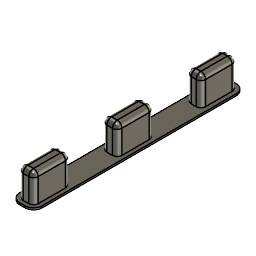
Buttons (Autodesk Fusion 360 design; units mm, degrees)
part number: 2026-07-23-09-26-05-520
Autodesk Fusion 360 part; units mm, degrees
sketch "Sketch1" plane through (0, 0, 0) normal (0, 0, 1) x (1, 0, 0)
  line L0 (-1.2, -11.25) -> (-1.2, 11.25)
  line L1 (-1.2, 11.25) -> (1.2, 11.25)
  line L2 (1.2, 11.25) -> (1.2, -11.25)
  line L3 (1.2, -11.25) -> (-1.2, -11.25)
  line L4 (0.76, 10.81) -> (0.76, 6.99)
  line L5 (-0.76, 6.99) -> (0.76, 6.99)
  line L6 (-0.76, 6.99) -> (-0.76, 10.81)
  line L7 (-0.76, 10.81) -> (0.76, 10.81)
  line L8 (-0.8, 1.95) -> (0.8, 1.95)
  line L9 (-0.8, -1.95) -> (-0.8, 1.95)
  line L10 (-0.8, -1.95) -> (0.8, -1.95)
  line L11 (0.8, 1.95) -> (0.8, -1.95)
  line L12 (-0.8, -6.95) -> (0.8, -6.95)
  line L13 (-0.8, -10.85) -> (-0.8, -6.95)
  line L14 (0.8, -10.85) -> (-0.8, -10.85)
  line L15 (0.8, -6.95) -> (0.8, -10.85)
extrude "Extrude1" add sketch "Sketch1" against normal blind 0.2 contours L0 L1 L2 L3 | L4 L5 L6 L7 | L8 L9 L10 L11 | L12 L13 L14 L15
extrude "Extrude2" add sketch "Sketch1" along normal blind 3 contours L4 L5 L6 L7 | L8 L9 L10 L11 | L12 L13 L14 L15
fillet "Fillet2" radius 0.5 24 edges at (-0.8, -10.85, 1.5) (-0.8, -6.95, 1.5) (0.8, -6.95, 1.5) (0.8, -10.85, 1.5) (-0.8, -8.9, 3) (0, -6.95, 3) (0.8, -8.9, 3) (0, -10.85, 3) (0, -1.95, 3) (-0.8, -1.95, 1.5) (-0.8, 0, 3) (-0.8, 1.95, 1.5) (0, 1.95, 3) (0.8, 1.95, 1.5) (0.8, 0, 3) (0.8, -1.95, 1.5) (-0.76, 10.81, 1.5) (0.76, 10.81, 1.5) (0, 10.81, 3) (-0.76, 8.9, 3) (0.76, 8.9, 3) (-0.76, 6.99, 1.5) (0, 6.99, 3) (0.76, 6.99, 1.5)
fillet "Fillet3" radius 0.9 4 edges at (-1.2, 11.25, -0.1) (1.2, 11.25, -0.1) (-1.2, -11.25, -0.1) (1.2, -11.25, -0.1)
